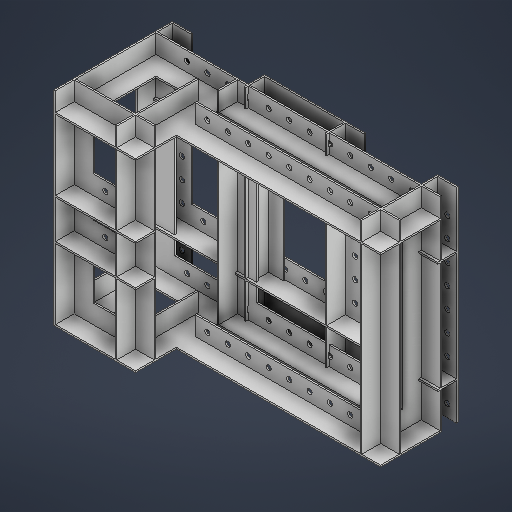
# Autodesk Inventor part: 01_Khung_Sat_V_Lo_Co_Hoc_Banh
Saved by Autodesk Inventor 2027.1 (Build 311270010, 270A)
## iProperties
Created: 2026-11-18
Part Number: 01_Khung_Sat_V_Lo_Co_Hoc_Banh
Material: Generic
Document SubType Name: Modeling
Designer: cuong
Density: 1 g/cm^3
Appearance: Default
Author: cuong
Autodesk Inventor part; units mm, degrees
(part 1 of 2)
ref_plane "Work Plane1" through (0, 0, 30) normal (0, 0, 1) x (1, 0, 0)
sketch "Sketch1" plane through (0, 0, 30) normal (0, 0, 1) x (1, 0, 0)
  line L0 (0, 45) -> (350, 45)
  line L1 (350, 45) -> (350, 70)
  line L2 (350, 70) -> (0, 70)
  line L3 (0, 70) -> (0, 45)
  constraints: 8 end point, 2 parallel, 1 horizontal, 1 perpendicular
extrude "Extrusion1" add sketch "Sketch1" along normal blind 2
ref_plane "Work Plane2" through (0, 0, 30) normal (0, 0, 1) x (1, 0, 0)
sketch "Sketch2" plane through (0, 0, 30) normal (0, 0, 1) x (1, 0, 0)
  line L0 (0, 45) -> (350, 45)
  line L1 (350, 45) -> (350, 47)
  line L2 (350, 47) -> (0, 47)
  line L3 (0, 47) -> (0, 45)
  constraints: 8 end point, 2 parallel, 1 horizontal, 1 perpendicular
extrude "Extrusion2" add sketch "Sketch2" along normal blind 25
ref_plane "Work Plane3" through (0, 0, 29) normal (0, 0, 1) x (1, 0, 0)
sketch "Sketch3" plane through (0, 0, 29) normal (0, 0, 1) x (1, 0, 0)
  circle A0 centre (15, 58.75) radius 3.2
  constraints: 1 centre point
extrude "Extrusion3" cut sketch "Sketch3" along normal blind 4
ref_plane "Work Plane4" through (0, 0, 29) normal (0, 0, 1) x (1, 0, 0)
sketch "Sketch4" plane through (0, 0, 29) normal (0, 0, 1) x (1, 0, 0)
  circle A0 centre (40, 58.75) radius 3.2
  constraints: 1 centre point
extrude "Extrusion4" cut sketch "Sketch4" along normal blind 4
ref_plane "Work Plane5" through (0, 0, 29) normal (0, 0, 1) x (1, 0, 0)
sketch "Sketch5" plane through (0, 0, 29) normal (0, 0, 1) x (1, 0, 0)
  circle A0 centre (65, 58.75) radius 3.2
  constraints: 1 centre point
extrude "Extrusion5" cut sketch "Sketch5" along normal blind 4
ref_plane "Work Plane6" through (0, 0, 29) normal (0, 0, 1) x (1, 0, 0)
sketch "Sketch6" plane through (0, 0, 29) normal (0, 0, 1) x (1, 0, 0)
  circle A0 centre (90, 58.75) radius 3.2
  constraints: 1 centre point
extrude "Extrusion6" cut sketch "Sketch6" along normal blind 4
ref_plane "Work Plane7" through (0, 0, 29) normal (0, 0, 1) x (1, 0, 0)
sketch "Sketch7" plane through (0, 0, 29) normal (0, 0, 1) x (1, 0, 0)
  circle A0 centre (115, 58.75) radius 3.2
  constraints: 1 centre point
extrude "Extrusion7" cut sketch "Sketch7" along normal blind 4
ref_plane "Work Plane8" through (0, 0, 29) normal (0, 0, 1) x (1, 0, 0)
sketch "Sketch8" plane through (0, 0, 29) normal (0, 0, 1) x (1, 0, 0)
  circle A0 centre (140, 58.75) radius 3.2
  constraints: 1 centre point
extrude "Extrusion8" cut sketch "Sketch8" along normal blind 4
ref_plane "Work Plane9" through (0, 0, 29) normal (0, 0, 1) x (1, 0, 0)
sketch "Sketch9" plane through (0, 0, 29) normal (0, 0, 1) x (1, 0, 0)
  circle A0 centre (165, 58.75) radius 3.2
  constraints: 1 centre point
extrude "Extrusion9" cut sketch "Sketch9" along normal blind 4
ref_plane "Work Plane10" through (0, 0, 29) normal (0, 0, 1) x (1, 0, 0)
sketch "Sketch10" plane through (0, 0, 29) normal (0, 0, 1) x (1, 0, 0)
  circle A0 centre (190, 58.75) radius 3.2
  constraints: 1 centre point
extrude "Extrusion10" cut sketch "Sketch10" along normal blind 4
ref_plane "Work Plane11" through (0, 0, 29) normal (0, 0, 1) x (1, 0, 0)
sketch "Sketch11" plane through (0, 0, 29) normal (0, 0, 1) x (1, 0, 0)
  circle A0 centre (215, 58.75) radius 3.2
  constraints: 1 centre point
extrude "Extrusion11" cut sketch "Sketch11" along normal blind 4
ref_plane "Work Plane12" through (0, 0, 29) normal (0, 0, 1) x (1, 0, 0)
sketch "Sketch12" plane through (0, 0, 29) normal (0, 0, 1) x (1, 0, 0)
  circle A0 centre (240, 58.75) radius 3.2
  constraints: 1 centre point
extrude "Extrusion12" cut sketch "Sketch12" along normal blind 4
ref_plane "Work Plane13" through (0, 0, 29) normal (0, 0, 1) x (1, 0, 0)
sketch "Sketch13" plane through (0, 0, 29) normal (0, 0, 1) x (1, 0, 0)
  circle A0 centre (265, 58.75) radius 3.2
  constraints: 1 centre point
extrude "Extrusion13" cut sketch "Sketch13" along normal blind 4
ref_plane "Work Plane14" through (0, 0, 29) normal (0, 0, 1) x (1, 0, 0)
sketch "Sketch14" plane through (0, 0, 29) normal (0, 0, 1) x (1, 0, 0)
  circle A0 centre (290, 58.75) radius 3.2
  constraints: 1 centre point
extrude "Extrusion14" cut sketch "Sketch14" along normal blind 4
ref_plane "Work Plane15" through (0, 0, 29) normal (0, 0, 1) x (1, 0, 0)
sketch "Sketch15" plane through (0, 0, 29) normal (0, 0, 1) x (1, 0, 0)
  circle A0 centre (315, 58.75) radius 3.2
  constraints: 1 centre point
extrude "Extrusion15" cut sketch "Sketch15" along normal blind 4
ref_plane "Work Plane16" through (0, 0, 30) normal (0, 0, 1) x (1, 0, 0)
sketch "Sketch16" plane through (0, 0, 30) normal (0, 0, 1) x (1, 0, 0)
  line L0 (0, 180) -> (350, 180)
  line L1 (350, 180) -> (350, 205)
  line L2 (350, 205) -> (0, 205)
  line L3 (0, 205) -> (0, 180)
  constraints: 8 end point, 2 parallel, 1 horizontal, 1 perpendicular
extrude "Extrusion16" add sketch "Sketch16" along normal blind 2
ref_plane "Work Plane17" through (0, 0, 30) normal (0, 0, 1) x (1, 0, 0)
sketch "Sketch17" plane through (0, 0, 30) normal (0, 0, 1) x (1, 0, 0)
  line L0 (0, 180) -> (350, 180)
  line L1 (350, 180) -> (350, 182)
  line L2 (350, 182) -> (0, 182)
  line L3 (0, 182) -> (0, 180)
  constraints: 8 end point, 2 parallel, 1 horizontal, 1 perpendicular
extrude "Extrusion17" add sketch "Sketch17" along normal blind 25
ref_plane "Work Plane18" through (0, 0, 29) normal (0, 0, 1) x (1, 0, 0)
sketch "Sketch18" plane through (0, 0, 29) normal (0, 0, 1) x (1, 0, 0)
  circle A0 centre (15, 193.75) radius 3.2
  constraints: 1 centre point
extrude "Extrusion18" cut sketch "Sketch18" along normal blind 4
ref_plane "Work Plane19" through (0, 0, 29) normal (0, 0, 1) x (1, 0, 0)
sketch "Sketch19" plane through (0, 0, 29) normal (0, 0, 1) x (1, 0, 0)
  circle A0 centre (40, 193.75) radius 3.2
  constraints: 1 centre point
extrude "Extrusion19" cut sketch "Sketch19" along normal blind 4
ref_plane "Work Plane20" through (0, 0, 29) normal (0, 0, 1) x (1, 0, 0)
sketch "Sketch20" plane through (0, 0, 29) normal (0, 0, 1) x (1, 0, 0)
  circle A0 centre (65, 193.75) radius 3.2
  constraints: 1 centre point
extrude "Extrusion20" cut sketch "Sketch20" along normal blind 4
ref_plane "Work Plane21" through (0, 0, 29) normal (0, 0, 1) x (1, 0, 0)
sketch "Sketch21" plane through (0, 0, 29) normal (0, 0, 1) x (1, 0, 0)
  circle A0 centre (90, 193.75) radius 3.2
  constraints: 1 centre point
extrude "Extrusion21" cut sketch "Sketch21" along normal blind 4
ref_plane "Work Plane22" through (0, 0, 29) normal (0, 0, 1) x (1, 0, 0)
sketch "Sketch22" plane through (0, 0, 29) normal (0, 0, 1) x (1, 0, 0)
  circle A0 centre (115, 193.75) radius 3.2
  constraints: 1 centre point
extrude "Extrusion22" cut sketch "Sketch22" along normal blind 4
ref_plane "Work Plane23" through (0, 0, 29) normal (0, 0, 1) x (1, 0, 0)
sketch "Sketch23" plane through (0, 0, 29) normal (0, 0, 1) x (1, 0, 0)
  circle A0 centre (140, 193.75) radius 3.2
  constraints: 1 centre point
extrude "Extrusion23" cut sketch "Sketch23" along normal blind 4
ref_plane "Work Plane24" through (0, 0, 29) normal (0, 0, 1) x (1, 0, 0)
sketch "Sketch24" plane through (0, 0, 29) normal (0, 0, 1) x (1, 0, 0)
  circle A0 centre (165, 193.75) radius 3.2
  constraints: 1 centre point
extrude "Extrusion24" cut sketch "Sketch24" along normal blind 4
ref_plane "Work Plane25" through (0, 0, 29) normal (0, 0, 1) x (1, 0, 0)
sketch "Sketch25" plane through (0, 0, 29) normal (0, 0, 1) x (1, 0, 0)
  circle A0 centre (190, 193.75) radius 3.2
  constraints: 1 centre point
extrude "Extrusion25" cut sketch "Sketch25" along normal blind 4
ref_plane "Work Plane26" through (0, 0, 29) normal (0, 0, 1) x (1, 0, 0)
sketch "Sketch26" plane through (0, 0, 29) normal (0, 0, 1) x (1, 0, 0)
  circle A0 centre (215, 193.75) radius 3.2
  constraints: 1 centre point
extrude "Extrusion26" cut sketch "Sketch26" along normal blind 4
ref_plane "Work Plane27" through (0, 0, 29) normal (0, 0, 1) x (1, 0, 0)
sketch "Sketch27" plane through (0, 0, 29) normal (0, 0, 1) x (1, 0, 0)
  circle A0 centre (240, 193.75) radius 3.2
  constraints: 1 centre point
extrude "Extrusion27" cut sketch "Sketch27" along normal blind 4
ref_plane "Work Plane28" through (0, 0, 29) normal (0, 0, 1) x (1, 0, 0)
sketch "Sketch28" plane through (0, 0, 29) normal (0, 0, 1) x (1, 0, 0)
  circle A0 centre (265, 193.75) radius 3.2
  constraints: 1 centre point
extrude "Extrusion28" cut sketch "Sketch28" along normal blind 4
ref_plane "Work Plane29" through (0, 0, 29) normal (0, 0, 1) x (1, 0, 0)
sketch "Sketch29" plane through (0, 0, 29) normal (0, 0, 1) x (1, 0, 0)
  circle A0 centre (290, 193.75) radius 3.2
  constraints: 1 centre point
extrude "Extrusion29" cut sketch "Sketch29" along normal blind 4
ref_plane "Work Plane30" through (0, 0, 29) normal (0, 0, 1) x (1, 0, 0)
sketch "Sketch30" plane through (0, 0, 29) normal (0, 0, 1) x (1, 0, 0)
  circle A0 centre (315, 193.75) radius 3.2
  constraints: 1 centre point
extrude "Extrusion30" cut sketch "Sketch30" along normal blind 4
ref_plane "Work Plane31" through (0, 0, 30) normal (0, 0, 1) x (1, 0, 0)
sketch "Sketch31" plane through (0, 0, 30) normal (0, 0, 1) x (1, 0, 0)
  line L0 (0, 0) -> (25, 0)
  line L1 (25, 0) -> (25, 250)
  line L2 (25, 250) -> (0, 250)
  line L3 (0, 250) -> (0, 0)
  constraints: 8 end point, 2 parallel, 1 horizontal, 1 perpendicular
extrude "Extrusion31" add sketch "Sketch31" along normal blind 2
ref_plane "Work Plane32" through (0, 0, 30) normal (0, 0, 1) x (1, 0, 0)
sketch "Sketch32" plane through (0, 0, 30) normal (0, 0, 1) x (1, 0, 0)
  line L0 (0, 0) -> (2, 0)
  line L1 (2, 0) -> (2, 250)
  line L2 (2, 250) -> (0, 250)
  line L3 (0, 250) -> (0, 0)
  constraints: 8 end point, 2 parallel, 1 horizontal, 1 perpendicular
extrude "Extrusion32" add sketch "Sketch32" along normal blind 25
ref_plane "Work Plane33" through (0, 0, 29) normal (0, 0, 1) x (1, 0, 0)
sketch "Sketch33" plane through (0, 0, 29) normal (0, 0, 1) x (1, 0, 0)
  circle A0 centre (13.75, 15) radius 3.2
  constraints: 1 centre point
extrude "Extrusion33" cut sketch "Sketch33" along normal blind 4
ref_plane "Work Plane34" through (0, 0, 29) normal (0, 0, 1) x (1, 0, 0)
sketch "Sketch34" plane through (0, 0, 29) normal (0, 0, 1) x (1, 0, 0)
  circle A0 centre (13.75, 40) radius 3.2
  constraints: 1 centre point
extrude "Extrusion34" cut sketch "Sketch34" along normal blind 4
ref_plane "Work Plane35" through (0, 0, 29) normal (0, 0, 1) x (1, 0, 0)
sketch "Sketch35" plane through (0, 0, 29) normal (0, 0, 1) x (1, 0, 0)
  circle A0 centre (13.75, 65) radius 3.2
  constraints: 1 centre point
extrude "Extrusion35" cut sketch "Sketch35" along normal blind 4
ref_plane "Work Plane36" through (0, 0, 29) normal (0, 0, 1) x (1, 0, 0)
sketch "Sketch36" plane through (0, 0, 29) normal (0, 0, 1) x (1, 0, 0)
  circle A0 centre (13.75, 90) radius 3.2
  constraints: 1 centre point
extrude "Extrusion36" cut sketch "Sketch36" along normal blind 4
ref_plane "Work Plane37" through (0, 0, 29) normal (0, 0, 1) x (1, 0, 0)
sketch "Sketch37" plane through (0, 0, 29) normal (0, 0, 1) x (1, 0, 0)
  circle A0 centre (13.75, 115) radius 3.2
  constraints: 1 centre point
extrude "Extrusion37" cut sketch "Sketch37" along normal blind 4
ref_plane "Work Plane38" through (0, 0, 29) normal (0, 0, 1) x (1, 0, 0)
sketch "Sketch38" plane through (0, 0, 29) normal (0, 0, 1) x (1, 0, 0)
  circle A0 centre (13.75, 140) radius 3.2
  constraints: 1 centre point
extrude "Extrusion38" cut sketch "Sketch38" along normal blind 4
ref_plane "Work Plane39" through (0, 0, 29) normal (0, 0, 1) x (1, 0, 0)
sketch "Sketch39" plane through (0, 0, 29) normal (0, 0, 1) x (1, 0, 0)
  circle A0 centre (13.75, 165) radius 3.2
  constraints: 1 centre point
extrude "Extrusion39" cut sketch "Sketch39" along normal blind 4
ref_plane "Work Plane40" through (0, 0, 29) normal (0, 0, 1) x (1, 0, 0)
sketch "Sketch40" plane through (0, 0, 29) normal (0, 0, 1) x (1, 0, 0)
  circle A0 centre (13.75, 190) radius 3.2
  constraints: 1 centre point
extrude "Extrusion40" cut sketch "Sketch40" along normal blind 4
ref_plane "Work Plane41" through (0, 0, 29) normal (0, 0, 1) x (1, 0, 0)
sketch "Sketch41" plane through (0, 0, 29) normal (0, 0, 1) x (1, 0, 0)
  circle A0 centre (13.75, 215) radius 3.2
  constraints: 1 centre point
extrude "Extrusion41" cut sketch "Sketch41" along normal blind 4
ref_plane "Work Plane42" through (0, 0, 30) normal (0, 0, 1) x (1, 0, 0)
sketch "Sketch42" plane through (0, 0, 30) normal (0, 0, 1) x (1, 0, 0)
  line L0 (113, 0) -> (138, 0)
  line L1 (138, 0) -> (138, 250)
  line L2 (138, 250) -> (113, 250)
  line L3 (113, 250) -> (113, 0)
  constraints: 8 end point, 2 parallel, 1 horizontal, 1 perpendicular
extrude "Extrusion42" add sketch "Sketch42" along normal blind 2
ref_plane "Work Plane43" through (0, 0, 30) normal (0, 0, 1) x (1, 0, 0)
sketch "Sketch43" plane through (0, 0, 30) normal (0, 0, 1) x (1, 0, 0)
  line L0 (113, 0) -> (115, 0)
  line L1 (115, 0) -> (115, 250)
  line L2 (115, 250) -> (113, 250)
  line L3 (113, 250) -> (113, 0)
  constraints: 8 end point, 2 parallel, 1 horizontal, 1 perpendicular
extrude "Extrusion43" add sketch "Sketch43" along normal blind 25
ref_plane "Work Plane44" through (0, 0, 29) normal (0, 0, 1) x (1, 0, 0)
sketch "Sketch44" plane through (0, 0, 29) normal (0, 0, 1) x (1, 0, 0)
  circle A0 centre (126.75, 15) radius 3.2
  constraints: 1 centre point
extrude "Extrusion44" cut sketch "Sketch44" along normal blind 4
ref_plane "Work Plane45" through (0, 0, 29) normal (0, 0, 1) x (1, 0, 0)
sketch "Sketch45" plane through (0, 0, 29) normal (0, 0, 1) x (1, 0, 0)
  circle A0 centre (126.75, 40) radius 3.2
  constraints: 1 centre point
extrude "Extrusion45" cut sketch "Sketch45" along normal blind 4
ref_plane "Work Plane46" through (0, 0, 29) normal (0, 0, 1) x (1, 0, 0)
sketch "Sketch46" plane through (0, 0, 29) normal (0, 0, 1) x (1, 0, 0)
  circle A0 centre (126.75, 65) radius 3.2
  constraints: 1 centre point
extrude "Extrusion46" cut sketch "Sketch46" along normal blind 4
ref_plane "Work Plane47" through (0, 0, 29) normal (0, 0, 1) x (1, 0, 0)
sketch "Sketch47" plane through (0, 0, 29) normal (0, 0, 1) x (1, 0, 0)
  circle A0 centre (126.75, 90) radius 3.2
  constraints: 1 centre point
extrude "Extrusion47" cut sketch "Sketch47" along normal blind 4
ref_plane "Work Plane48" through (0, 0, 29) normal (0, 0, 1) x (1, 0, 0)
sketch "Sketch48" plane through (0, 0, 29) normal (0, 0, 1) x (1, 0, 0)
  circle A0 centre (126.75, 115) radius 3.2
  constraints: 1 centre point
extrude "Extrusion48" cut sketch "Sketch48" along normal blind 4
ref_plane "Work Plane49" through (0, 0, 29) normal (0, 0, 1) x (1, 0, 0)
sketch "Sketch49" plane through (0, 0, 29) normal (0, 0, 1) x (1, 0, 0)
  circle A0 centre (126.75, 140) radius 3.2
  constraints: 1 centre point
extrude "Extrusion49" cut sketch "Sketch49" along normal blind 4
ref_plane "Work Plane50" through (0, 0, 29) normal (0, 0, 1) x (1, 0, 0)
sketch "Sketch50" plane through (0, 0, 29) normal (0, 0, 1) x (1, 0, 0)
  circle A0 centre (126.75, 165) radius 3.2
  constraints: 1 centre point
extrude "Extrusion50" cut sketch "Sketch50" along normal blind 4
ref_plane "Work Plane51" through (0, 0, 29) normal (0, 0, 1) x (1, 0, 0)
sketch "Sketch51" plane through (0, 0, 29) normal (0, 0, 1) x (1, 0, 0)
  circle A0 centre (126.75, 190) radius 3.2
  constraints: 1 centre point
extrude "Extrusion51" cut sketch "Sketch51" along normal blind 4
ref_plane "Work Plane52" through (0, 0, 29) normal (0, 0, 1) x (1, 0, 0)
sketch "Sketch52" plane through (0, 0, 29) normal (0, 0, 1) x (1, 0, 0)
  circle A0 centre (126.75, 215) radius 3.2
  constraints: 1 centre point
extrude "Extrusion52" cut sketch "Sketch52" along normal blind 4
ref_plane "Work Plane53" through (0, 0, 30) normal (0, 0, 1) x (1, 0, 0)
sketch "Sketch53" plane through (0, 0, 30) normal (0, 0, 1) x (1, 0, 0)
  line L0 (212, 0) -> (237, 0)
  line L1 (237, 0) -> (237, 250)
  line L2 (237, 250) -> (212, 250)
  line L3 (212, 250) -> (212, 0)
  constraints: 8 end point, 2 parallel, 1 horizontal, 1 perpendicular
extrude "Extrusion53" add sketch "Sketch53" along normal blind 2
ref_plane "Work Plane54" through (0, 0, 30) normal (0, 0, 1) x (1, 0, 0)
sketch "Sketch54" plane through (0, 0, 30) normal (0, 0, 1) x (1, 0, 0)
  line L0 (212, 0) -> (214, 0)
  line L1 (214, 0) -> (214, 250)
  line L2 (214, 250) -> (212, 250)
  line L3 (212, 250) -> (212, 0)
  constraints: 8 end point, 2 parallel, 1 horizontal, 1 perpendicular
extrude "Extrusion54" add sketch "Sketch54" along normal blind 25
ref_plane "Work Plane55" through (0, 0, 29) normal (0, 0, 1) x (1, 0, 0)
sketch "Sketch55" plane through (0, 0, 29) normal (0, 0, 1) x (1, 0, 0)
  circle A0 centre (225.75, 15) radius 3.2
  constraints: 1 centre point
extrude "Extrusion55" cut sketch "Sketch55" along normal blind 4
ref_plane "Work Plane56" through (0, 0, 29) normal (0, 0, 1) x (1, 0, 0)
sketch "Sketch56" plane through (0, 0, 29) normal (0, 0, 1) x (1, 0, 0)
  circle A0 centre (225.75, 40) radius 3.2
  constraints: 1 centre point
extrude "Extrusion56" cut sketch "Sketch56" along normal blind 4
ref_plane "Work Plane57" through (0, 0, 29) normal (0, 0, 1) x (1, 0, 0)
sketch "Sketch57" plane through (0, 0, 29) normal (0, 0, 1) x (1, 0, 0)
  circle A0 centre (225.75, 65) radius 3.2
  constraints: 1 centre point
extrude "Extrusion57" cut sketch "Sketch57" along normal blind 4
ref_plane "Work Plane58" through (0, 0, 29) normal (0, 0, 1) x (1, 0, 0)
sketch "Sketch58" plane through (0, 0, 29) normal (0, 0, 1) x (1, 0, 0)
  circle A0 centre (225.75, 90) radius 3.2
  constraints: 1 centre point
extrude "Extrusion58" cut sketch "Sketch58" along normal blind 4
ref_plane "Work Plane59" through (0, 0, 29) normal (0, 0, 1) x (1, 0, 0)
sketch "Sketch59" plane through (0, 0, 29) normal (0, 0, 1) x (1, 0, 0)
  circle A0 centre (225.75, 115) radius 3.2
  constraints: 1 centre point
extrude "Extrusion59" cut sketch "Sketch59" along normal blind 4
ref_plane "Work Plane60" through (0, 0, 29) normal (0, 0, 1) x (1, 0, 0)
sketch "Sketch60" plane through (0, 0, 29) normal (0, 0, 1) x (1, 0, 0)
  circle A0 centre (225.75, 140) radius 3.2
  constraints: 1 centre point
extrude "Extrusion60" cut sketch "Sketch60" along normal blind 4
ref_plane "Work Plane61" through (0, 0, 29) normal (0, 0, 1) x (1, 0, 0)
sketch "Sketch61" plane through (0, 0, 29) normal (0, 0, 1) x (1, 0, 0)
  circle A0 centre (225.75, 165) radius 3.2
  constraints: 1 centre point
extrude "Extrusion61" cut sketch "Sketch61" along normal blind 4
ref_plane "Work Plane62" through (0, 0, 29) normal (0, 0, 1) x (1, 0, 0)
sketch "Sketch62" plane through (0, 0, 29) normal (0, 0, 1) x (1, 0, 0)
  circle A0 centre (225.75, 190) radius 3.2
  constraints: 1 centre point
extrude "Extrusion62" cut sketch "Sketch62" along normal blind 4
ref_plane "Work Plane63" through (0, 0, 29) normal (0, 0, 1) x (1, 0, 0)
sketch "Sketch63" plane through (0, 0, 29) normal (0, 0, 1) x (1, 0, 0)
  circle A0 centre (225.75, 215) radius 3.2
  constraints: 1 centre point
extrude "Extrusion63" cut sketch "Sketch63" along normal blind 4
ref_plane "Work Plane64" through (0, 0, 30) normal (0, 0, 1) x (1, 0, 0)
sketch "Sketch64" plane through (0, 0, 30) normal (0, 0, 1) x (1, 0, 0)
  line L0 (325, 0) -> (350, 0)
  line L1 (350, 0) -> (350, 250)
  line L2 (350, 250) -> (325, 250)
  line L3 (325, 250) -> (325, 0)
  constraints: 8 end point, 2 parallel, 1 horizontal, 1 perpendicular
extrude "Extrusion64" add sketch "Sketch64" along normal blind 2
ref_plane "Work Plane65" through (0, 0, 30) normal (0, 0, 1) x (1, 0, 0)
sketch "Sketch65" plane through (0, 0, 30) normal (0, 0, 1) x (1, 0, 0)
  line L0 (325, 0) -> (327, 0)
  line L1 (327, 0) -> (327, 250)
  line L2 (327, 250) -> (325, 250)
  line L3 (325, 250) -> (325, 0)
  constraints: 8 end point, 2 parallel, 1 horizontal, 1 perpendicular
extrude "Extrusion65" add sketch "Sketch65" along normal blind 25
ref_plane "Work Plane66" through (0, 0, 29) normal (0, 0, 1) x (1, 0, 0)
sketch "Sketch66" plane through (0, 0, 29) normal (0, 0, 1) x (1, 0, 0)
  circle A0 centre (338.75, 15) radius 3.2
  constraints: 1 centre point
extrude "Extrusion66" cut sketch "Sketch66" along normal blind 4
ref_plane "Work Plane67" through (0, 0, 29) normal (0, 0, 1) x (1, 0, 0)
sketch "Sketch67" plane through (0, 0, 29) normal (0, 0, 1) x (1, 0, 0)
  circle A0 centre (338.75, 40) radius 3.2
  constraints: 1 centre point
extrude "Extrusion67" cut sketch "Sketch67" along normal blind 4
ref_plane "Work Plane68" through (0, 0, 29) normal (0, 0, 1) x (1, 0, 0)
sketch "Sketch68" plane through (0, 0, 29) normal (0, 0, 1) x (1, 0, 0)
  circle A0 centre (338.75, 65) radius 3.2
  constraints: 1 centre point
extrude "Extrusion68" cut sketch "Sketch68" along normal blind 4
ref_plane "Work Plane69" through (0, 0, 29) normal (0, 0, 1) x (1, 0, 0)
sketch "Sketch69" plane through (0, 0, 29) normal (0, 0, 1) x (1, 0, 0)
  circle A0 centre (338.75, 90) radius 3.2
  constraints: 1 centre point
extrude "Extrusion69" cut sketch "Sketch69" along normal blind 4
ref_plane "Work Plane70" through (0, 0, 29) normal (0, 0, 1) x (1, 0, 0)
sketch "Sketch70" plane through (0, 0, 29) normal (0, 0, 1) x (1, 0, 0)
  circle A0 centre (338.75, 115) radius 3.2
  constraints: 1 centre point
extrude "Extrusion70" cut sketch "Sketch70" along normal blind 4
ref_plane "Work Plane71" through (0, 0, 29) normal (0, 0, 1) x (1, 0, 0)
sketch "Sketch71" plane through (0, 0, 29) normal (0, 0, 1) x (1, 0, 0)
  circle A0 centre (338.75, 140) radius 3.2
  constraints: 1 centre point
extrude "Extrusion71" cut sketch "Sketch71" along normal blind 4
ref_plane "Work Plane72" through (0, 0, 29) normal (0, 0, 1) x (1, 0, 0)
sketch "Sketch72" plane through (0, 0, 29) normal (0, 0, 1) x (1, 0, 0)
  circle A0 centre (338.75, 165) radius 3.2
  constraints: 1 centre point
extrude "Extrusion72" cut sketch "Sketch72" along normal blind 4
ref_plane "Work Plane73" through (0, 0, 29) normal (0, 0, 1) x (1, 0, 0)
sketch "Sketch73" plane through (0, 0, 29) normal (0, 0, 1) x (1, 0, 0)
  circle A0 centre (338.75, 190) radius 3.2
  constraints: 1 centre point
extrude "Extrusion73" cut sketch "Sketch73" along normal blind 4
ref_plane "Work Plane74" through (0, 0, 29) normal (0, 0, 1) x (1, 0, 0)
sketch "Sketch74" plane through (0, 0, 29) normal (0, 0, 1) x (1, 0, 0)
  circle A0 centre (338.75, 215) radius 3.2
  constraints: 1 centre point
extrude "Extrusion74" cut sketch "Sketch74" along normal blind 4
ref_plane "Work Plane75" through (0, 0, 30) normal (0, 0, 1) x (1, 0, 0)
sketch "Sketch75" plane through (0, 0, 30) normal (0, 0, 1) x (1, 0, 0)
  line L0 (113, 0) -> (237, 0)
  line L1 (237, 0) -> (237, 25)
  line L2 (237, 25) -> (113, 25)
  line L3 (113, 25) -> (113, 0)
  constraints: 8 end point, 2 parallel, 1 horizontal, 1 perpendicular
extrude "Extrusion75" add sketch "Sketch75" along normal blind 2
ref_plane "Work Plane76" through (0, 0, 30) normal (0, 0, 1) x (1, 0, 0)
sketch "Sketch76" plane through (0, 0, 30) normal (0, 0, 1) x (1, 0, 0)
  line L0 (113, 0) -> (237, 0)
  line L1 (237, 0) -> (237, 2)
  line L2 (237, 2) -> (113, 2)
  line L3 (113, 2) -> (113, 0)
  constraints: 8 end point, 2 parallel, 1 horizontal, 1 perpendicular
extrude "Extrusion76" add sketch "Sketch76" along normal blind 25
ref_plane "Work Plane77" through (0, 0, 30) normal (0, 0, 1) x (1, 0, 0)
sketch "Sketch77" plane through (0, 0, 30) normal (0, 0, 1) x (1, 0, 0)
  line L0 (113, 225) -> (237, 225)
  line L1 (237, 225) -> (237, 250)
  line L2 (237, 250) -> (113, 250)
  line L3 (113, 250) -> (113, 225)
  constraints: 8 end point, 2 parallel, 1 horizontal, 1 perpendicular
extrude "Extrusion77" add sketch "Sketch77" along normal blind 2
ref_plane "Work Plane78" through (0, 0, 30) normal (0, 0, 1) x (1, 0, 0)
sketch "Sketch78" plane through (0, 0, 30) normal (0, 0, 1) x (1, 0, 0)
  line L0 (113, 225) -> (237, 225)
  line L1 (237, 225) -> (237, 227)
  line L2 (237, 227) -> (113, 227)
  line L3 (113, 227) -> (113, 225)
  constraints: 8 end point, 2 parallel, 1 horizontal, 1 perpendicular
extrude "Extrusion78" add sketch "Sketch78" along normal blind 25
ref_plane "Work Plane79" through (0, 0, 32) normal (0, 0, 1) x (1, 0, 0)
sketch "Sketch79" plane through (0, 0, 32) normal (0, 0, 1) x (1, 0, 0)
  line L0 (120, 45) -> (140, 45)
  line L1 (140, 45) -> (140, 205)
  line L2 (140, 205) -> (120, 205)
  line L3 (120, 205) -> (120, 45)
  constraints: 8 end point, 2 parallel, 1 horizontal, 1 perpendicular
extrude "Extrusion79" add sketch "Sketch79" along normal blind 2
ref_plane "Work Plane80" through (0, 0, 32) normal (0, 0, 1) x (1, 0, 0)
sketch "Sketch80" plane through (0, 0, 32) normal (0, 0, 1) x (1, 0, 0)
  line L0 (120, 45) -> (122, 45)
  line L1 (122, 45) -> (122, 205)
  line L2 (122, 205) -> (120, 205)
  line L3 (120, 205) -> (120, 45)
  constraints: 8 end point, 2 parallel, 1 horizontal, 1 perpendicular
extrude "Extrusion80" add sketch "Sketch80" along normal blind 20
ref_plane "Work Plane81" through (0, 0, 32) normal (0, 0, 1) x (1, 0, 0)
sketch "Sketch81" plane through (0, 0, 32) normal (0, 0, 1) x (1, 0, 0)
  line L0 (260, 45) -> (280, 45)
  line L1 (280, 45) -> (280, 205)
  line L2 (280, 205) -> (260, 205)
  line L3 (260, 205) -> (260, 45)
  constraints: 8 end point, 2 parallel, 1 horizontal, 1 perpendicular
extrude "Extrusion81" add sketch "Sketch81" along normal blind 2
ref_plane "Work Plane82" through (0, 0, 32) normal (0, 0, 1) x (1, 0, 0)
sketch "Sketch82" plane through (0, 0, 32) normal (0, 0, 1) x (1, 0, 0)
  line L0 (260, 45) -> (262, 45)
  line L1 (262, 45) -> (262, 205)
  line L2 (262, 205) -> (260, 205)
  line L3 (260, 205) -> (260, 45)
  constraints: 8 end point, 2 parallel, 1 horizontal, 1 perpendicular
extrude "Extrusion82" add sketch "Sketch82" along normal blind 20
ref_plane "Work Plane83" through (0, 0, 50) normal (0, 0, 1) x (1, 0, 0)
sketch "Sketch83" plane through (0, 0, 50) normal (0, 0, 1) x (1, 0, 0)
  line L0 (0, 0) -> (350, 0)
  line L1 (350, 0) -> (350, 25)
  line L2 (350, 25) -> (0, 25)
  line L3 (0, 25) -> (0, 0)
  constraints: 8 end point, 2 parallel, 1 horizontal, 1 perpendicular
extrude "Extrusion83" add sketch "Sketch83" along normal blind 2
ref_plane "Work Plane84" through (0, 0, 50) normal (0, 0, 1) x (1, 0, 0)
sketch "Sketch84" plane through (0, 0, 50) normal (0, 0, 1) x (1, 0, 0)
  line L0 (0, 0) -> (350, 0)
  line L1 (350, 0) -> (350, 2)
  line L2 (350, 2) -> (0, 2)
  line L3 (0, 2) -> (0, 0)
  constraints: 8 end point, 2 parallel, 1 horizontal, 1 perpendicular
extrude "Extrusion84" add sketch "Sketch84" along normal blind 25
ref_plane "Work Plane85" through (0, 0, 49) normal (0, 0, 1) x (1, 0, 0)
sketch "Sketch85" plane through (0, 0, 49) normal (0, 0, 1) x (1, 0, 0)
  circle A0 centre (15, 13.75) radius 3.2
  constraints: 1 centre point
extrude "Extrusion85" cut sketch "Sketch85" along normal blind 4
ref_plane "Work Plane86" through (0, 0, 49) normal (0, 0, 1) x (1, 0, 0)
sketch "Sketch86" plane through (0, 0, 49) normal (0, 0, 1) x (1, 0, 0)
  circle A0 centre (40, 13.75) radius 3.2
  constraints: 1 centre point
extrude "Extrusion86" cut sketch "Sketch86" along normal blind 4
ref_plane "Work Plane87" through (0, 0, 49) normal (0, 0, 1) x (1, 0, 0)
sketch "Sketch87" plane through (0, 0, 49) normal (0, 0, 1) x (1, 0, 0)
  circle A0 centre (65, 13.75) radius 3.2
  constraints: 1 centre point
extrude "Extrusion87" cut sketch "Sketch87" along normal blind 4
ref_plane "Work Plane88" through (0, 0, 49) normal (0, 0, 1) x (1, 0, 0)
sketch "Sketch88" plane through (0, 0, 49) normal (0, 0, 1) x (1, 0, 0)
  circle A0 centre (90, 13.75) radius 3.2
  constraints: 1 centre point
extrude "Extrusion88" cut sketch "Sketch88" along normal blind 4
ref_plane "Work Plane89" through (0, 0, 49) normal (0, 0, 1) x (1, 0, 0)
sketch "Sketch89" plane through (0, 0, 49) normal (0, 0, 1) x (1, 0, 0)
  circle A0 centre (115, 13.75) radius 3.2
  constraints: 1 centre point
extrude "Extrusion89" cut sketch "Sketch89" along normal blind 4
ref_plane "Work Plane90" through (0, 0, 49) normal (0, 0, 1) x (1, 0, 0)
sketch "Sketch90" plane through (0, 0, 49) normal (0, 0, 1) x (1, 0, 0)
  circle A0 centre (140, 13.75) radius 3.2
  constraints: 1 centre point
extrude "Extrusion90" cut sketch "Sketch90" along normal blind 4
ref_plane "Work Plane91" through (0, 0, 49) normal (0, 0, 1) x (1, 0, 0)
sketch "Sketch91" plane through (0, 0, 49) normal (0, 0, 1) x (1, 0, 0)
  circle A0 centre (165, 13.75) radius 3.2
  constraints: 1 centre point
extrude "Extrusion91" cut sketch "Sketch91" along normal blind 4
ref_plane "Work Plane92" through (0, 0, 49) normal (0, 0, 1) x (1, 0, 0)
sketch "Sketch92" plane through (0, 0, 49) normal (0, 0, 1) x (1, 0, 0)
  circle A0 centre (190, 13.75) radius 3.2
  constraints: 1 centre point
extrude "Extrusion92" cut sketch "Sketch92" along normal blind 4
ref_plane "Work Plane93" through (0, 0, 49) normal (0, 0, 1) x (1, 0, 0)
sketch "Sketch93" plane through (0, 0, 49) normal (0, 0, 1) x (1, 0, 0)
  circle A0 centre (215, 13.75) radius 3.2
  constraints: 1 centre point
extrude "Extrusion93" cut sketch "Sketch93" along normal blind 4
ref_plane "Work Plane94" through (0, 0, 49) normal (0, 0, 1) x (1, 0, 0)
sketch "Sketch94" plane through (0, 0, 49) normal (0, 0, 1) x (1, 0, 0)
  circle A0 centre (240, 13.75) radius 3.2
  constraints: 1 centre point
extrude "Extrusion94" cut sketch "Sketch94" along normal blind 4
ref_plane "Work Plane95" through (0, 0, 49) normal (0, 0, 1) x (1, 0, 0)
sketch "Sketch95" plane through (0, 0, 49) normal (0, 0, 1) x (1, 0, 0)
  circle A0 centre (265, 13.75) radius 3.2
  constraints: 1 centre point
extrude "Extrusion95" cut sketch "Sketch95" along normal blind 4
ref_plane "Work Plane96" through (0, 0, 49) normal (0, 0, 1) x (1, 0, 0)
sketch "Sketch96" plane through (0, 0, 49) normal (0, 0, 1) x (1, 0, 0)
  circle A0 centre (290, 13.75) radius 3.2
  constraints: 1 centre point
extrude "Extrusion96" cut sketch "Sketch96" along normal blind 4
ref_plane "Work Plane97" through (0, 0, 49) normal (0, 0, 1) x (1, 0, 0)
sketch "Sketch97" plane through (0, 0, 49) normal (0, 0, 1) x (1, 0, 0)
  circle A0 centre (315, 13.75) radius 3.2
  constraints: 1 centre point
extrude "Extrusion97" cut sketch "Sketch97" along normal blind 4
ref_plane "Work Plane98" through (0, 0, 50) normal (0, 0, 1) x (1, 0, 0)
sketch "Sketch98" plane through (0, 0, 50) normal (0, 0, 1) x (1, 0, 0)
  line L0 (0, 225) -> (350, 225)
  line L1 (350, 225) -> (350, 250)
  line L2 (350, 250) -> (0, 250)
  line L3 (0, 250) -> (0, 225)
  constraints: 8 end point, 2 parallel, 1 horizontal, 1 perpendicular
extrude "Extrusion98" add sketch "Sketch98" along normal blind 2
ref_plane "Work Plane99" through (0, 0, 50) normal (0, 0, 1) x (1, 0, 0)
sketch "Sketch99" plane through (0, 0, 50) normal (0, 0, 1) x (1, 0, 0)
  line L0 (0, 225) -> (350, 225)
  line L1 (350, 225) -> (350, 227)
  line L2 (350, 227) -> (0, 227)
  line L3 (0, 227) -> (0, 225)
  constraints: 8 end point, 2 parallel, 1 horizontal, 1 perpendicular
extrude "Extrusion99" add sketch "Sketch99" along normal blind 25
ref_plane "Work Plane100" through (0, 0, 49) normal (0, 0, 1) x (1, 0, 0)
sketch "Sketch100" plane through (0, 0, 49) normal (0, 0, 1) x (1, 0, 0)
  circle A0 centre (15, 238.75) radius 3.2
  constraints: 1 centre point
extrude "Extrusion100" cut sketch "Sketch100" along normal blind 4
ref_plane "Work Plane101" through (0, 0, 49) normal (0, 0, 1) x (1, 0, 0)
sketch "Sketch101" plane through (0, 0, 49) normal (0, 0, 1) x (1, 0, 0)
  circle A0 centre (40, 238.75) radius 3.2
  constraints: 1 centre point
extrude "Extrusion101" cut sketch "Sketch101" along normal blind 4
ref_plane "Work Plane102" through (0, 0, 49) normal (0, 0, 1) x (1, 0, 0)
sketch "Sketch102" plane through (0, 0, 49) normal (0, 0, 1) x (1, 0, 0)
  circle A0 centre (65, 238.75) radius 3.2
  constraints: 1 centre point
extrude "Extrusion102" cut sketch "Sketch102" along normal blind 4
ref_plane "Work Plane103" through (0, 0, 49) normal (0, 0, 1) x (1, 0, 0)
sketch "Sketch103" plane through (0, 0, 49) normal (0, 0, 1) x (1, 0, 0)
  circle A0 centre (90, 238.75) radius 3.2
  constraints: 1 centre point
extrude "Extrusion103" cut sketch "Sketch103" along normal blind 4
ref_plane "Work Plane104" through (0, 0, 49) normal (0, 0, 1) x (1, 0, 0)
sketch "Sketch104" plane through (0, 0, 49) normal (0, 0, 1) x (1, 0, 0)
  circle A0 centre (115, 238.75) radius 3.2
  constraints: 1 centre point
extrude "Extrusion104" cut sketch "Sketch104" along normal blind 4
ref_plane "Work Plane105" through (0, 0, 49) normal (0, 0, 1) x (1, 0, 0)
sketch "Sketch105" plane through (0, 0, 49) normal (0, 0, 1) x (1, 0, 0)
  circle A0 centre (140, 238.75) radius 3.2
  constraints: 1 centre point
extrude "Extrusion105" cut sketch "Sketch105" along normal blind 4
ref_plane "Work Plane106" through (0, 0, 49) normal (0, 0, 1) x (1, 0, 0)
sketch "Sketch106" plane through (0, 0, 49) normal (0, 0, 1) x (1, 0, 0)
  circle A0 centre (165, 238.75) radius 3.2
  constraints: 1 centre point
extrude "Extrusion106" cut sketch "Sketch106" along normal blind 4
ref_plane "Work Plane107" through (0, 0, 49) normal (0, 0, 1) x (1, 0, 0)
sketch "Sketch107" plane through (0, 0, 49) normal (0, 0, 1) x (1, 0, 0)
  circle A0 centre (190, 238.75) radius 3.2
  constraints: 1 centre point
extrude "Extrusion107" cut sketch "Sketch107" along normal blind 4
ref_plane "Work Plane108" through (0, 0, 49) normal (0, 0, 1) x (1, 0, 0)
sketch "Sketch108" plane through (0, 0, 49) normal (0, 0, 1) x (1, 0, 0)
  circle A0 centre (215, 238.75) radius 3.2
  constraints: 1 centre point
extrude "Extrusion108" cut sketch "Sketch108" along normal blind 4
ref_plane "Work Plane109" through (0, 0, 49) normal (0, 0, 1) x (1, 0, 0)
sketch "Sketch109" plane through (0, 0, 49) normal (0, 0, 1) x (1, 0, 0)
  circle A0 centre (240, 238.75) radius 3.2
  constraints: 1 centre point
extrude "Extrusion109" cut sketch "Sketch109" along normal blind 4
ref_plane "Work Plane110" through (0, 0, 49) normal (0, 0, 1) x (1, 0, 0)
sketch "Sketch110" plane through (0, 0, 49) normal (0, 0, 1) x (1, 0, 0)
  circle A0 centre (265, 238.75) radius 3.2
  constraints: 1 centre point
extrude "Extrusion110" cut sketch "Sketch110" along normal blind 4
ref_plane "Work Plane111" through (0, 0, 49) normal (0, 0, 1) x (1, 0, 0)
sketch "Sketch111" plane through (0, 0, 49) normal (0, 0, 1) x (1, 0, 0)
  circle A0 centre (290, 238.75) radius 3.2
  constraints: 1 centre point
extrude "Extrusion111" cut sketch "Sketch111" along normal blind 4
ref_plane "Work Plane112" through (0, 0, 49) normal (0, 0, 1) x (1, 0, 0)
sketch "Sketch112" plane through (0, 0, 49) normal (0, 0, 1) x (1, 0, 0)
  circle A0 centre (315, 238.75) radius 3.2
  constraints: 1 centre point
extrude "Extrusion112" cut sketch "Sketch112" along normal blind 4
ref_plane "Work Plane113" through (0, 0, 50) normal (0, 0, 1) x (1, 0, 0)
sketch "Sketch113" plane through (0, 0, 50) normal (0, 0, 1) x (1, 0, 0)
  line L0 (0, 0) -> (25, 0)
  line L1 (25, 0) -> (25, 250)
  line L2 (25, 250) -> (0, 250)
  line L3 (0, 250) -> (0, 0)
  constraints: 8 end point, 2 parallel, 1 horizontal, 1 perpendicular
extrude "Extrusion113" add sketch "Sketch113" along normal blind 2
ref_plane "Work Plane114" through (0, 0, 50) normal (0, 0, 1) x (1, 0, 0)
sketch "Sketch114" plane through (0, 0, 50) normal (0, 0, 1) x (1, 0, 0)
  line L0 (0, 0) -> (2, 0)
  line L1 (2, 0) -> (2, 250)
  line L2 (2, 250) -> (0, 250)
  line L3 (0, 250) -> (0, 0)
  constraints: 8 end point, 2 parallel, 1 horizontal, 1 perpendicular
extrude "Extrusion114" add sketch "Sketch114" along normal blind 25
ref_plane "Work Plane115" through (0, 0, 50) normal (0, 0, 1) x (1, 0, 0)
sketch "Sketch115" plane through (0, 0, 50) normal (0, 0, 1) x (1, 0, 0)
  line L0 (100, 0) -> (125, 0)
  line L1 (125, 0) -> (125, 250)
  line L2 (125, 250) -> (100, 250)
  line L3 (100, 250) -> (100, 0)
  constraints: 8 end point, 2 parallel, 1 horizontal, 1 perpendicular
extrude "Extrusion115" add sketch "Sketch115" along normal blind 2
ref_plane "Work Plane116" through (0, 0, 50) normal (0, 0, 1) x (1, 0, 0)
sketch "Sketch116" plane through (0, 0, 50) normal (0, 0, 1) x (1, 0, 0)
  line L0 (100, 0) -> (102, 0)
  line L1 (102, 0) -> (102, 250)
  line L2 (102, 250) -> (100, 250)
  line L3 (100, 250) -> (100, 0)
  constraints: 8 end point, 2 parallel, 1 horizontal, 1 perpendicular
extrude "Extrusion116" add sketch "Sketch116" along normal blind 25
ref_plane "Work Plane117" through (0, 0, 50) normal (0, 0, 1) x (1, 0, 0)
sketch "Sketch117" plane through (0, 0, 50) normal (0, 0, 1) x (1, 0, 0)
  line L0 (325, 0) -> (350, 0)
  line L1 (350, 0) -> (350, 250)
  line L2 (350, 250) -> (325, 250)
  line L3 (325, 250) -> (325, 0)
  constraints: 8 end point, 2 parallel, 1 horizontal, 1 perpendicular
extrude "Extrusion117" add sketch "Sketch117" along normal blind 2
ref_plane "Work Plane118" through (0, 0, 50) normal (0, 0, 1) x (1, 0, 0)
sketch "Sketch118" plane through (0, 0, 50) normal (0, 0, 1) x (1, 0, 0)
  line L0 (325, 0) -> (327, 0)
  line L1 (327, 0) -> (327, 250)
  line L2 (327, 250) -> (325, 250)
  line L3 (325, 250) -> (325, 0)
  constraints: 8 end point, 2 parallel, 1 horizontal, 1 perpendicular
extrude "Extrusion118" add sketch "Sketch118" along normal blind 25
ref_plane "Work Plane119" through (0, 0, 75) normal (0, 0, 1) x (1, 0, 0)
sketch "Sketch119" plane through (0, 0, 75) normal (0, 0, 1) x (1, 0, 0)
  line L0 (0, 0) -> (25, 0)
  line L1 (25, 0) -> (25, 2)
  line L2 (25, 2) -> (0, 2)
  line L3 (0, 2) -> (0, 0)
  constraints: 8 end point, 2 parallel, 1 horizontal, 1 perpendicular
extrude "Extrusion119" add sketch "Sketch119" along normal blind 100
ref_plane "Work Plane120" through (0, 0, 75) normal (0, 0, 1) x (1, 0, 0)
sketch "Sketch120" plane through (0, 0, 75) normal (0, 0, 1) x (1, 0, 0)
  line L0 (0, 0) -> (2, 0)
  line L1 (2, 0) -> (2, 25)
  line L2 (2, 25) -> (0, 25)
  line L3 (0, 25) -> (0, 0)
  constraints: 8 end point, 2 parallel, 1 horizontal, 1 perpendicular
extrude "Extrusion120" add sketch "Sketch120" along normal blind 100
ref_plane "Work Plane121" through (0, 0, 75) normal (0, 0, 1) x (1, 0, 0)
sketch "Sketch121" plane through (0, 0, 75) normal (0, 0, 1) x (1, 0, 0)
  line L0 (0, 225) -> (25, 225)
  line L1 (25, 225) -> (25, 227)
  line L2 (25, 227) -> (0, 227)
  line L3 (0, 227) -> (0, 225)
  constraints: 8 end point, 2 parallel, 1 horizontal, 1 perpendicular
extrude "Extrusion121" add sketch "Sketch121" along normal blind 100
ref_plane "Work Plane122" through (0, 0, 75) normal (0, 0, 1) x (1, 0, 0)
sketch "Sketch122" plane through (0, 0, 75) normal (0, 0, 1) x (1, 0, 0)
  line L0 (0, 225) -> (2, 225)
  line L1 (2, 225) -> (2, 250)
  line L2 (2, 250) -> (0, 250)
  line L3 (0, 250) -> (0, 225)
  constraints: 8 end point, 2 parallel, 1 horizontal, 1 perpendicular
extrude "Extrusion122" add sketch "Sketch122" along normal blind 100
ref_plane "Work Plane123" through (0, 0, 75) normal (0, 0, 1) x (1, 0, 0)
sketch "Sketch123" plane through (0, 0, 75) normal (0, 0, 1) x (1, 0, 0)
  line L0 (75, 0) -> (100, 0)
  line L1 (100, 0) -> (100, 2)
  line L2 (100, 2) -> (75, 2)
  line L3 (75, 2) -> (75, 0)
  constraints: 8 end point, 2 parallel, 1 horizontal, 1 perpendicular
extrude "Extrusion123" add sketch "Sketch123" along normal blind 100
ref_plane "Work Plane124" through (0, 0, 75) normal (0, 0, 1) x (1, 0, 0)
sketch "Sketch124" plane through (0, 0, 75) normal (0, 0, 1) x (1, 0, 0)
  line L0 (75, 0) -> (77, 0)
  line L1 (77, 0) -> (77, 25)
  line L2 (77, 25) -> (75, 25)
  line L3 (75, 25) -> (75, 0)
  constraints: 8 end point, 2 parallel, 1 horizontal, 1 perpendicular
extrude "Extrusion124" add sketch "Sketch124" along normal blind 100
ref_plane "Work Plane125" through (0, 0, 75) normal (0, 0, 1) x (1, 0, 0)
sketch "Sketch125" plane through (0, 0, 75) normal (0, 0, 1) x (1, 0, 0)
  line L0 (75, 225) -> (100, 225)
  line L1 (100, 225) -> (100, 227)
  line L2 (100, 227) -> (75, 227)
  line L3 (75, 227) -> (75, 225)
  constraints: 8 end point, 2 parallel, 1 horizontal, 1 perpendicular
extrude "Extrusion125" add sketch "Sketch125" along normal blind 100
ref_plane "Work Plane126" through (0, 0, 75) normal (0, 0, 1) x (1, 0, 0)
sketch "Sketch126" plane through (0, 0, 75) normal (0, 0, 1) x (1, 0, 0)
  line L0 (75, 225) -> (77, 225)
  line L1 (77, 225) -> (77, 250)
  line L2 (77, 250) -> (75, 250)
  line L3 (75, 250) -> (75, 225)
  constraints: 8 end point, 2 parallel, 1 horizontal, 1 perpendicular
extrude "Extrusion126" add sketch "Sketch126" along normal blind 100
ref_plane "Work Plane127" through (0, 0, 150) normal (0, 0, 1) x (1, 0, 0)
sketch "Sketch127" plane through (0, 0, 150) normal (0, 0, 1) x (1, 0, 0)
  line L0 (0, 0) -> (100, 0)
  line L1 (100, 0) -> (100, 25)
  line L2 (100, 25) -> (0, 25)
  line L3 (0, 25) -> (0, 0)
  constraints: 8 end point, 2 parallel, 1 horizontal, 1 perpendicular
extrude "Extrusion127" add sketch "Sketch127" along normal blind 2
ref_plane "Work Plane128" through (0, 0, 150) normal (0, 0, 1) x (1, 0, 0)
sketch "Sketch128" plane through (0, 0, 150) normal (0, 0, 1) x (1, 0, 0)
  line L0 (0, 0) -> (100, 0)
  line L1 (100, 0) -> (100, 2)
  line L2 (100, 2) -> (0, 2)
  line L3 (0, 2) -> (0, 0)
  constraints: 8 end point, 2 parallel, 1 horizontal, 1 perpendicular
extrude "Extrusion128" add sketch "Sketch128" along normal blind 25
ref_plane "Work Plane129" through (0, 0, 150) normal (0, 0, 1) x (1, 0, 0)
sketch "Sketch129" plane through (0, 0, 150) normal (0, 0, 1) x (1, 0, 0)
  line L0 (0, 225) -> (100, 225)
  line L1 (100, 225) -> (100, 250)
  line L2 (100, 250) -> (0, 250)
  line L3 (0, 250) -> (0, 225)
  constraints: 8 end point, 2 parallel, 1 horizontal, 1 perpendicular
extrude "Extrusion129" add sketch "Sketch129" along normal blind 2
ref_plane "Work Plane130" through (0, 0, 150) normal (0, 0, 1) x (1, 0, 0)
sketch "Sketch130" plane through (0, 0, 150) normal (0, 0, 1) x (1, 0, 0)
  line L0 (0, 225) -> (100, 225)
  line L1 (100, 225) -> (100, 227)
  line L2 (100, 227) -> (0, 227)
  line L3 (0, 227) -> (0, 225)
  constraints: 8 end point, 2 parallel, 1 horizontal, 1 perpendicular
extrude "Extrusion130" add sketch "Sketch130" along normal blind 25
ref_plane "Work Plane131" through (0, 0, 150) normal (0, 0, 1) x (1, 0, 0)
sketch "Sketch131" plane through (0, 0, 150) normal (0, 0, 1) x (1, 0, 0)
  line L0 (0, 88) -> (100, 88)
  line L1 (100, 88) -> (100, 113)
  line L2 (100, 113) -> (0, 113)
  line L3 (0, 113) -> (0, 88)
  constraints: 8 end point, 2 parallel, 1 horizontal, 1 perpendicular
extrude "Extrusion131" add sketch "Sketch131" along normal blind 2
ref_plane "Work Plane132" through (0, 0, 150) normal (0, 0, 1) x (1, 0, 0)
sketch "Sketch132" plane through (0, 0, 150) normal (0, 0, 1) x (1, 0, 0)
  line L0 (0, 88) -> (100, 88)
  line L1 (100, 88) -> (100, 90)
  line L2 (100, 90) -> (0, 90)
  line L3 (0, 90) -> (0, 88)
  constraints: 8 end point, 2 parallel, 1 horizontal, 1 perpendicular
extrude "Extrusion132" add sketch "Sketch132" along normal blind 25
ref_plane "Work Plane133" through (0, 0, 149) normal (0, 0, 1) x (1, 0, 0)
sketch "Sketch133" plane through (0, 0, 149) normal (0, 0, 1) x (1, 0, 0)
  circle A0 centre (15, 101.75) radius 3.2
  constraints: 1 centre point
extrude "Extrusion133" cut sketch "Sketch133" along normal blind 4
ref_plane "Work Plane134" through (0, 0, 149) normal (0, 0, 1) x (1, 0, 0)
sketch "Sketch134" plane through (0, 0, 149) normal (0, 0, 1) x (1, 0, 0)
  circle A0 centre (40, 101.75) radius 3.2
  constraints: 1 centre point
extrude "Extrusion134" cut sketch "Sketch134" along normal blind 4
ref_plane "Work Plane135" through (0, 0, 149) normal (0, 0, 1) x (1, 0, 0)
sketch "Sketch135" plane through (0, 0, 149) normal (0, 0, 1) x (1, 0, 0)
  circle A0 centre (65, 101.75) radius 3.2
  constraints: 1 centre point
extrude "Extrusion135" cut sketch "Sketch135" along normal blind 4
ref_plane "Work Plane136" through (0, 0, 150) normal (0, 0, 1) x (1, 0, 0)
sketch "Sketch136" plane through (0, 0, 150) normal (0, 0, 1) x (1, 0, 0)
  line L0 (0, 137) -> (100, 137)
  line L1 (100, 137) -> (100, 162)
  line L2 (100, 162) -> (0, 162)
  line L3 (0, 162) -> (0, 137)
  constraints: 8 end point, 2 parallel, 1 horizontal, 1 perpendicular
extrude "Extrusion136" add sketch "Sketch136" along normal blind 2
ref_plane "Work Plane137" through (0, 0, 150) normal (0, 0, 1) x (1, 0, 0)
sketch "Sketch137" plane through (0, 0, 150) normal (0, 0, 1) x (1, 0, 0)
  line L0 (0, 137) -> (100, 137)
  line L1 (100, 137) -> (100, 139)
  line L2 (100, 139) -> (0, 139)
  line L3 (0, 139) -> (0, 137)
  constraints: 8 end point, 2 parallel, 1 horizontal, 1 perpendicular
extrude "Extrusion137" add sketch "Sketch137" along normal blind 25
ref_plane "Work Plane138" through (0, 0, 149) normal (0, 0, 1) x (1, 0, 0)
sketch "Sketch138" plane through (0, 0, 149) normal (0, 0, 1) x (1, 0, 0)
  circle A0 centre (15, 150.75) radius 3.2
  constraints: 1 centre point
extrude "Extrusion138" cut sketch "Sketch138" along normal blind 4
ref_plane "Work Plane139" through (0, 0, 149) normal (0, 0, 1) x (1, 0, 0)
sketch "Sketch139" plane through (0, 0, 149) normal (0, 0, 1) x (1, 0, 0)
  circle A0 centre (40, 150.75) radius 3.2
  constraints: 1 centre point
extrude "Extrusion139" cut sketch "Sketch139" along normal blind 4
ref_plane "Work Plane140" through (0, 0, 149) normal (0, 0, 1) x (1, 0, 0)
sketch "Sketch140" plane through (0, 0, 149) normal (0, 0, 1) x (1, 0, 0)
  circle A0 centre (65, 150.75) radius 3.2
  constraints: 1 centre point
extrude "Extrusion140" cut sketch "Sketch140" along normal blind 4
ref_plane "Work Plane141" through (0, 0, 150) normal (0, 0, 1) x (1, 0, 0)
sketch "Sketch141" plane through (0, 0, 150) normal (0, 0, 1) x (1, 0, 0)
  line L0 (0, 0) -> (25, 0)
  line L1 (25, 0) -> (25, 250)
  line L2 (25, 250) -> (0, 250)
  line L3 (0, 250) -> (0, 0)
  constraints: 8 end point, 2 parallel, 1 horizontal, 1 perpendicular
extrude "Extrusion141" add sketch "Sketch141" along normal blind 2
ref_plane "Work Plane142" through (0, 0, 150) normal (0, 0, 1) x (1, 0, 0)
sketch "Sketch142" plane through (0, 0, 150) normal (0, 0, 1) x (1, 0, 0)
  line L0 (0, 0) -> (2, 0)
  line L1 (2, 0) -> (2, 250)
  line L2 (2, 250) -> (0, 250)
  line L3 (0, 250) -> (0, 0)
  constraints: 8 end point, 2 parallel, 1 horizontal, 1 perpendicular
extrude "Extrusion142" add sketch "Sketch142" along normal blind 25
ref_plane "Work Plane143" through (0, 0, 150) normal (0, 0, 1) x (1, 0, 0)
sketch "Sketch143" plane through (0, 0, 150) normal (0, 0, 1) x (1, 0, 0)
  line L0 (75, 0) -> (100, 0)
  line L1 (100, 0) -> (100, 250)
  line L2 (100, 250) -> (75, 250)
  line L3 (75, 250) -> (75, 0)
  constraints: 8 end point, 2 parallel, 1 horizontal, 1 perpendicular
extrude "Extrusion143" add sketch "Sketch143" along normal blind 2
ref_plane "Work Plane144" through (0, 0, 150) normal (0, 0, 1) x (1, 0, 0)
sketch "Sketch144" plane through (0, 0, 150) normal (0, 0, 1) x (1, 0, 0)
  line L0 (75, 0) -> (77, 0)
  line L1 (77, 0) -> (77, 250)
  line L2 (77, 250) -> (75, 250)
  line L3 (75, 250) -> (75, 0)
  constraints: 8 end point, 2 parallel, 1 horizontal, 1 perpendicular
extrude "Extrusion144" add sketch "Sketch144" along normal blind 25
ref_plane "Work Plane145" through (0, 0, 100) normal (0, 0, 1) x (1, 0, 0)
sketch "Sketch145" plane through (0, 0, 100) normal (0, 0, 1) x (1, 0, 0)
  line L0 (100, 0) -> (350, 0)
  line L1 (350, 0) -> (350, 25)
  line L2 (350, 25) -> (100, 25)
  line L3 (100, 25) -> (100, 0)
  constraints: 8 end point, 2 parallel, 1 horizontal, 1 perpendicular
extrude "Extrusion145" add sketch "Sketch145" along normal blind 2
ref_plane "Work Plane146" through (0, 0, 100) normal (0, 0, 1) x (1, 0, 0)
sketch "Sketch146" plane through (0, 0, 100) normal (0, 0, 1) x (1, 0, 0)
  line L0 (100, 0) -> (350, 0)
  line L1 (350, 0) -> (350, 2)
  line L2 (350, 2) -> (100, 2)
  line L3 (100, 2) -> (100, 0)
  constraints: 8 end point, 2 parallel, 1 horizontal, 1 perpendicular
extrude "Extrusion146" add sketch "Sketch146" along normal blind 25
ref_plane "Work Plane147" through (0, 0, 99) normal (0, 0, 1) x (1, 0, 0)
sketch "Sketch147" plane through (0, 0, 99) normal (0, 0, 1) x (1, 0, 0)
  circle A0 centre (115, 13.75) radius 3.2
  constraints: 1 centre point
extrude "Extrusion147" cut sketch "Sketch147" along normal blind 4
ref_plane "Work Plane148" through (0, 0, 99) normal (0, 0, 1) x (1, 0, 0)
sketch "Sketch148" plane through (0, 0, 99) normal (0, 0, 1) x (1, 0, 0)
  circle A0 centre (140, 13.75) radius 3.2
  constraints: 1 centre point
extrude "Extrusion148" cut sketch "Sketch148" along normal blind 4
ref_plane "Work Plane149" through (0, 0, 99) normal (0, 0, 1) x (1, 0, 0)
sketch "Sketch149" plane through (0, 0, 99) normal (0, 0, 1) x (1, 0, 0)
  circle A0 centre (165, 13.75) radius 3.2
  constraints: 1 centre point
extrude "Extrusion149" cut sketch "Sketch149" along normal blind 4
ref_plane "Work Plane150" through (0, 0, 99) normal (0, 0, 1) x (1, 0, 0)
sketch "Sketch150" plane through (0, 0, 99) normal (0, 0, 1) x (1, 0, 0)
  circle A0 centre (190, 13.75) radius 3.2
  constraints: 1 centre point
extrude "Extrusion150" cut sketch "Sketch150" along normal blind 4
ref_plane "Work Plane151" through (0, 0, 99) normal (0, 0, 1) x (1, 0, 0)